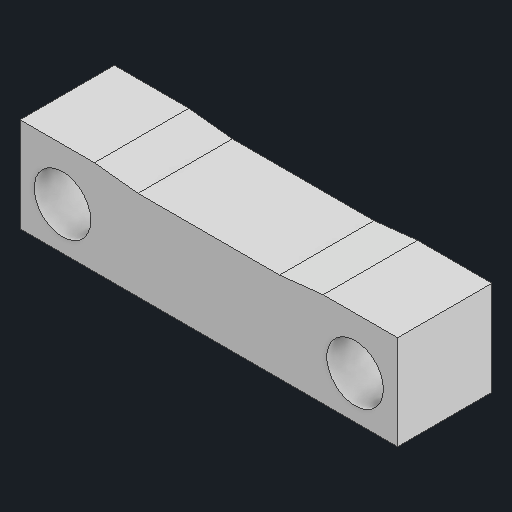
# Autodesk Inventor part: 扭力模块结构挡板
Saved by Autodesk Inventor 2025 (Build 290162000, 162)
## iProperties
Created: 2025-08-27
Part Number: 扭力模块结构挡板
Material: 常规
Document SubType Name: Modeling
Designer: HZD
Density: 1 g/cm^3
Appearance: 默认
Author: HZD
Autodesk Inventor part; units mm, degrees
ref_plane "YZ Plane" through (0, 0, 0) normal (1, 0, 0) x (0, 1, 0)
ref_plane "XZ Plane" through (0, 0, 0) normal (0, 1, 0) x (-1, 0, 0)
ref_plane "XY Plane" through (0, 0, 0) normal (0, 0, 1) x (1, 0, 0)
sketch "草图1" plane through (0, 0, 0) normal (0, 0, 1) x (1, 0, 0)
  line L0 (4, -1) -> (-4, -1)
  line L1 (-4, -1) -> (-4, 1)
  line L2 (-4, 1) -> (4, 1)
  line L3 (4, 1) -> (4, -1)
  line L4 (4, -1) -> (-4, 1) construction
  line L5 (-4, -1) -> (4, 1) construction
  circle A0 centre (3.1, -0.1) radius 0.6
  line L6 (0, -1) -> (0, 1)
  circle A1 centre (-3.1, -0.1) radius 0.6
  point P0 (0, 0)
  dimension "d0" = 8
  dimension "d1" = 2
  dimension "d4" = 1.2
  dimension "d12" = 0.9
  dimension "d13" = 0.9
  constraints: 14 end point, 4 midpoint, 2 centre point, 2 parallel, 1 horizontal, 1 perpendicular, 1 symmetric about line, 1 other
  measures "d0" distance of L1.end L2.end
  measures "d1" distance of L2.end L0.start
  measures "d4" diameter of A0
  measures "d12" distance from line of A0.centre L0
  measures "d13" distance from line of A0.centre L3
extrude "拉伸1" add sketch "草图1" along normal blind 2
sketch "草图2" plane through (0, 0, 0) normal (0, 0, -1) x (-1, 0, 0)
  line L0 (1.5, 0.9) -> (-1.5, 0.9)
  line L1 (-1.5, 0.9) -> (-1.5, 1)
  line L2 (-1.5, 1) -> (1.5, 1)
  line L3 (1.5, 1) -> (1.5, 0.9)
  line L4 (1.5, 0.9) -> (-1.5, 1) construction
  line L5 (-1.5, 0.9) -> (1.5, 1) construction
  line L6 (4, -1) -> (-4, -1) projected
  line L7 (-4, 1) -> (4, 1) projected
  line L8 (-1.5, 0.9) -> (-2.4228, 1)
  line L9 (0, 1) -> (0, -1)
  line L10 (1.5, 0.9) -> (2.4228, 1)
  line L11 (-2.5, 0.9) -> (2.5, 0.9) projected
  point P0 (0, 0)
  point P1 (0, 0.95)
  point P2 (2.4228, 1)
  dimension "d6" = 3
  constraints: 18 end point, 4 midpoint, 2 collinear, 2 parallel, 2 point on line, 1 horizontal, 1 perpendicular, 1 symmetric about line
  measures "d6" distance of L1.end L2.end
extrude "拉伸2" cut sketch "草图2" against normal blind 3
